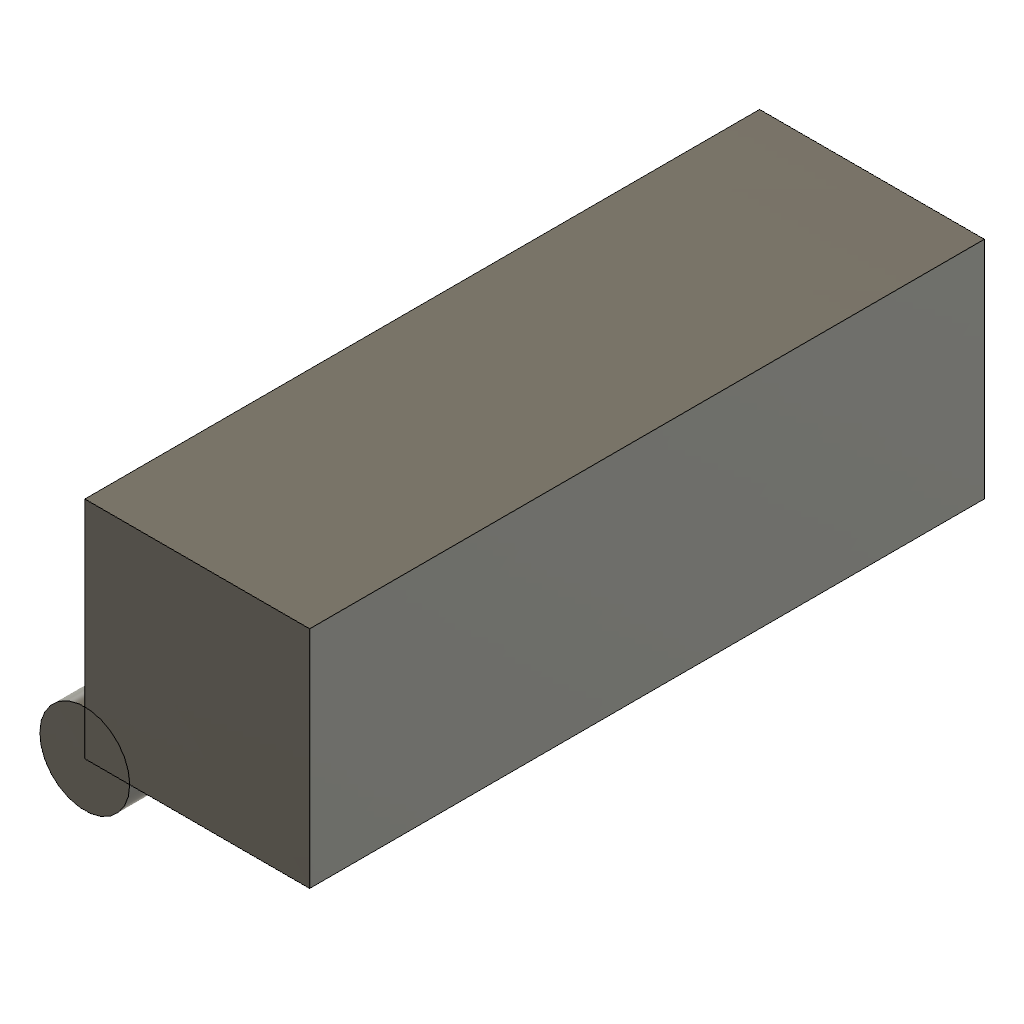
brep_edge_circular (Autodesk Fusion 360 design; units mm, degrees)
part number: 2026-10-20-23-07-32-395
Autodesk Fusion 360 part; units mm, degrees
sketch "PipeEdgeSupportSketch" plane through (0, 0, 0) normal (0, 0, 1) x (1, 0, 0)
  line L0 (0, 0) -> (10, 0)
  line L1 (10, 0) -> (10, 10)
  line L2 (10, 10) -> (0, 10)
  line L3 (0, 10) -> (0, 0)
extrude "PipeEdgeSupportExtrude" add sketch "PipeEdgeSupportSketch" along normal blind 30 makes body 1
pipe "ProbePipePath" add diameter 4 along 1 edges at (0, 0, 15) separate body on bodies 1 makes body 2
named bodies: "PipePathSupportBody"
